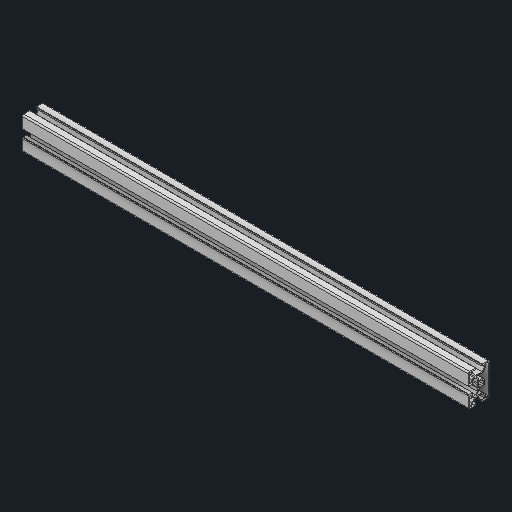
# Autodesk Inventor part: 3842993710_STRUT PROFILE 30x45_h150_260914151454532
Saved by Autodesk Inventor 2026 (Build 300175050, 175E)
## iProperties
Created: 2026-09-14
Material: Generic
Document SubType Name: Modeling
Designer: Anura
Density: 1 g/cm^3
Appearance: Default
Catalog Web Link: www.boschrexroth.com/brl
Description: STRUT PROFILE 30x45
Vendor: Bosch Rexroth AG - BRL
Mass: 660 g
Surface Area: 3005.56 cm^2
Volume: 243.421 cm^3
Package size: 1
Material no.: 3842993710.0
Part name: STRUT PROFILE 30x45
Parameters: LP=619,7MM;
Weight: 0.681680139701
Product group: MGE
HS code: 76042100.0
Format Version: 0
MTproCodeNo: 76042100.0
MTproDesignation: STRUT PROFILE 30x45
MTproParam1: 2#0@Profile type=30x45|Length L [mm]=619,70921791|Number of finishes=0|
MtproPline: 20
MTproPrice: 0.0
MTproWeight: 0.681680139701
MtproWeightUnit: kg/m
Major Version: 4
Minor Version: 0
OrderNo: 3842993710.0
Param: LP=619,7MM;
ProductId: Bosch Rexroth AG
Sending System: Bosch Rexroth AG
FileDetail: HD
Author: Anura
Autodesk Inventor part; units mm, degrees
ref_plane "YZ Plane" through (0, 0, 0) normal (1, 0, 0) x (0, 1, 0)
ref_plane "XZ Plane" through (0, 0, 0) normal (0, 1, 0) x (-1, 0, 0)
ref_plane "XY Plane" through (0, 0, 0) normal (0, 0, 1) x (1, 0, 0)
sketch "Sketch1" plane through (0, 0, 0) normal (1, 0, 0) x (0, 1, 0)
  line L0 (-7.5, 13) -> (-11.55, 13)
  line L1 (-11.55, 13) -> (-11.55, 8.7674)
  line L2 (-11.55, 8.7674) -> (-12.7846, 8.256)
  line L3 (-12.7846, 8.256) -> (-16.7787, 12.25)
  line L4 (-16.7787, 12.25) -> (-21, 12.25)
  line L5 (-21, 12.25) -> (-21, 14.5)
  arc A0 (-19.5, 16) -> (-21, 14.5) centre (-19.5, 14.5) ccw
  line L6 (-19.5, 16) -> (-7.5, 16)
  line L7 (-7.5, 16) -> (-7.5, 13)
  line L8 (3.7049, 2.3055) -> (3.2171, 1.7241)
  arc A1 (3.2171, -1.7241) -> (3.2171, 1.7241) centre (0, 0) ccw
  line L9 (3.2171, -1.7241) -> (3.7049, -2.3055)
  line L10 (3.7049, -2.3055) -> (2.3055, -3.7049)
  line L11 (2.3055, -3.7049) -> (1.7241, -3.2171)
  arc A2 (-1.7241, -3.2171) -> (1.7241, -3.2171) centre (0, 0) ccw
  line L12 (-1.7241, -3.2171) -> (-2.3055, -3.7049)
  line L13 (-2.3055, -3.7049) -> (-3.7049, -2.3055)
  line L14 (-3.7049, -2.3055) -> (-3.2171, -1.7241)
  arc A3 (-3.2171, 1.7241) -> (-3.2171, -1.7241) centre (0, 0) ccw
  line L15 (-3.2171, 1.7241) -> (-3.7049, 2.3055)
  line L16 (-3.7049, 2.3055) -> (-2.3055, 3.7049)
  line L17 (-2.3055, 3.7049) -> (-1.7241, 3.2171)
  arc A4 (1.7241, 3.2171) -> (-1.7241, 3.2171) centre (0, 0) ccw
  line L18 (1.7241, 3.2171) -> (2.3055, 3.7049)
  line L19 (2.3055, 3.7049) -> (3.7049, 2.3055)
  line L20 (12, 5.3826) -> (12, -2.4713)
  line L21 (12, -2.4713) -> (16.7787, -7.25)
  line L22 (16.7787, -7.25) -> (21, -7.25)
  line L23 (21, -7.25) -> (21, -10)
  arc A5 (20, -11) -> (21, -10) centre (20, -10) ccw
  line L24 (20, -11) -> (-20, -11)
  arc A6 (-21, -10) -> (-20, -11) centre (-20, -10) ccw
  line L25 (-21, -10) -> (-21, -7.25)
  line L26 (-21, -7.25) -> (-16.7787, -7.25)
  line L27 (-16.7787, -7.25) -> (-12, -2.4713)
  line L28 (-12, -2.4713) -> (-12, 5.3826)
  line L29 (-12, 5.3826) -> (-10.7654, 5.894)
  line L30 (-10.7654, 5.894) -> (-7.8713, 3)
  line L31 (-7.8713, 3) -> (-5, 3)
  line L32 (-5, 3) -> (-5, -3.2426)
  line L33 (-5, -3.2426) -> (-3.2426, -5)
  line L34 (-3.2426, -5) -> (3.2426, -5)
  line L35 (3.2426, -5) -> (5, -3.2426)
  line L36 (5, -3.2426) -> (5, 3)
  line L37 (5, 3) -> (7.8713, 3)
  line L38 (7.8713, 3) -> (10.7654, 5.894)
  line L39 (10.7654, 5.894) -> (12, 5.3826)
  line L40 (11.55, 8.7674) -> (11.55, 13)
  line L41 (11.55, 13) -> (7.5, 13)
  line L42 (7.5, 13) -> (7.5, 16)
  line L43 (7.5, 16) -> (19.5, 16)
  arc A7 (21, 14.5) -> (19.5, 16) centre (19.5, 14.5) ccw
  line L44 (21, 14.5) -> (21, 12.25)
  line L45 (21, 12.25) -> (16.7787, 12.25)
  line L46 (16.7787, 12.25) -> (12.7846, 8.256)
  line L47 (12.7846, 8.256) -> (11.55, 8.7674)
  line L48 (5.8, 17.5) -> (5.8, 16)
  line L49 (5.8, 16) -> (5, 16)
  line L50 (5, 16) -> (5, 11.5)
  line L51 (5, 11.5) -> (10.05, 11.5)
  line L52 (10.05, 11.5) -> (10.05, 7.3)
  line L53 (10.05, 7.3) -> (7.25, 4.5)
  line L54 (7.25, 4.5) -> (3.1225, 4.5)
  line L55 (3.1225, 4.5) -> (1.6013, 5)
  line L56 (1.6013, 5) -> (-1.6013, 5)
  line L57 (-1.6013, 5) -> (-3.1225, 4.5)
  line L58 (-3.1225, 4.5) -> (-7.25, 4.5)
  line L59 (-7.25, 4.5) -> (-10.05, 7.3)
  line L60 (-10.05, 7.3) -> (-10.05, 11.5)
  line L61 (-10.05, 11.5) -> (-5, 11.5)
  line L62 (-5, 11.5) -> (-5, 16)
  line L63 (-5, 16) -> (-5.8, 16)
  line L64 (-5.8, 16) -> (-5.8, 17.5)
  line L65 (-5.8, 17.5) -> (-20.5, 17.5)
  arc A8 (-20.5, 17.5) -> (-22.5, 15.5) centre (-20.5, 15.5) ccw
  line L66 (-22.5, 15.5) -> (-22.5, 7.05)
  line L67 (-22.5, 7.05) -> (-22, 7.05)
  line L68 (-22, 7.05) -> (-22, 6.55)
  line L69 (-22, 6.55) -> (-20.3, 6.55)
  line L70 (-20.3, 6.55) -> (-20.3, 10.75)
  line L71 (-20.3, 10.75) -> (-17.4, 10.75)
  line L72 (-17.4, 10.75) -> (-13.5, 6.85)
  line L73 (-13.5, 6.85) -> (-13.5, -1.85)
  line L74 (-13.5, -1.85) -> (-17.4, -5.75)
  line L75 (-17.4, -5.75) -> (-20.3, -5.75)
  line L76 (-20.3, -5.75) -> (-20.3, -1.55)
  line L77 (-20.3, -1.55) -> (-22, -1.55)
  line L78 (-22, -1.55) -> (-22, -2.05)
  line L79 (-22, -2.05) -> (-22.5, -2.05)
  line L80 (-22.5, -2.05) -> (-22.5, -10.5)
  arc A9 (-22.5, -10.5) -> (-20.5, -12.5) centre (-20.5, -10.5) ccw
  line L81 (-20.5, -12.5) -> (20.5, -12.5)
  arc A10 (20.5, -12.5) -> (22.5, -10.5) centre (20.5, -10.5) ccw
  line L82 (22.5, -10.5) -> (22.5, -2.05)
  line L83 (22.5, -2.05) -> (22, -2.05)
  line L84 (22, -2.05) -> (22, -1.55)
  line L85 (22, -1.55) -> (20.3, -1.55)
  line L86 (20.3, -1.55) -> (20.3, -5.75)
  line L87 (20.3, -5.75) -> (17.4, -5.75)
  line L88 (17.4, -5.75) -> (13.5, -1.85)
  line L89 (13.5, -1.85) -> (13.5, 6.85)
  line L90 (13.5, 6.85) -> (17.4, 10.75)
  line L91 (17.4, 10.75) -> (20.3, 10.75)
  line L92 (20.3, 10.75) -> (20.3, 6.55)
  line L93 (20.3, 6.55) -> (22, 6.55)
  line L94 (22, 6.55) -> (22, 7.05)
  line L95 (22, 7.05) -> (22.5, 7.05)
  line L96 (22.5, 7.05) -> (22.5, 15.5)
  arc A11 (22.5, 15.5) -> (20.5, 17.5) centre (20.5, 15.5) ccw
  line L97 (20.5, 17.5) -> (5.8, 17.5)
  point P0 (0, 0)
  constraints: 196 end point, 24 point on circle, 12 centre point
extrude "BR_Extrude" add sketch "Sketch1" along normal blind 299.8546 and the other way blind 319.8546
equation "\"extrude_1\" = 0.5 * BR_WP13_BR_WP1_Length_090614431418526 + Start_delta"
equation "\"extrude_2\" = 0.5 * BR_WP13_BR_WP1_Length_090614431418526 + End_delta"
equation "\"Start_delta\" = 0"
equation "\"BR_WP13_BR_WP1_Length_090614431418526\" = 599.709218"
equation "\"End_delta\" = 20"
body "Solid1"
